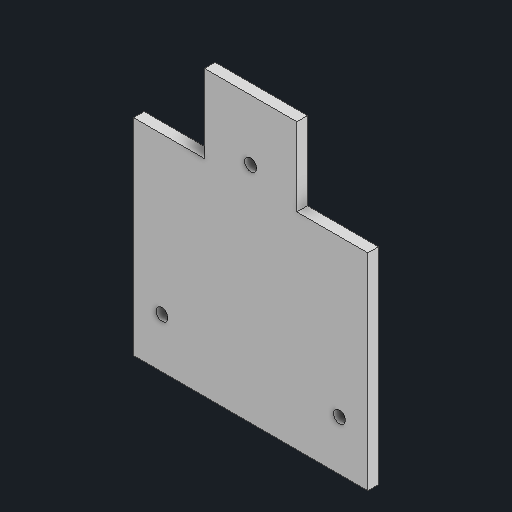
# Autodesk Inventor part: P4-04 Upper axle-support plate
Saved by Autodesk Inventor 2027.1 (Build 311270010, 270A)
## iProperties
Created: 2026-10-21
Part Number: P4-04 Upper axle-support plate
Material: Generic
Document SubType Name: Modeling
Designer: anshi
Mass: 13.0127 g
Surface Area: 98.207 cm^2
Volume: 13.0127 cm^3
Density: 1 g/cm^3
Appearance: Default
Author: anshi
Autodesk Inventor part; units mm, degrees
ref_plane "YZ Plane" through (0, 0, 0) normal (1, 0, 0) x (0, 1, 0)
ref_plane "XZ Plane" through (0, 0, 0) normal (0, 1, 0) x (-1, 0, 0)
ref_plane "XY Plane" through (0, 0, 0) normal (0, 0, 1) x (1, 0, 0)
sketch "Dimensioned base profile" plane through (0, 0, 0) normal (0, 0, 1) x (1, 0, 0)
  line L0 (-20, -26) -> (46, -26)
  line L1 (46, -26) -> (46, 32)
  line L2 (46, 32) -> (26, 32)
  line L3 (26, 32) -> (26, 54)
  line L4 (26, 54) -> (0, 54)
  line L5 (0, 54) -> (0, 32)
  line L6 (0, 32) -> (-20, 32)
  line L7 (-20, 32) -> (-20, -26)
  circle A0 centre (-12, -12) radius 1.7
  circle A1 centre (38, -12) radius 1.7
  circle A2 centre (13, 37) radius 1.7
  constraints: 16 end point, 3 centre point
extrude "Thickness 3 mm" add sketch "Dimensioned base profile" along normal blind 3
sketch "Axle pockets 4.10" plane through (0, 0, 0) normal (0, 0, 1) x (1, 0, 0)
  circle A0 centre (0, 22) radius 2.05
  circle A1 centre (26, 22) radius 2.05
  circle A2 centre (7, 46) radius 2.05
  circle A3 centre (19, 46) radius 2.05
  constraints: 4 centre point
extrude "Axle pockets depth 2" cut sketch "Axle pockets 4.10" along normal blind 2
equation "\"NominalThickness\" = 3"
body "Solid1"
